Autodesk Fusion 360 part; units mm, degrees
(part 2 of 6)
  spline S17 degree 5 poles (14.0851, -2.1614) (14.0795, -2.1564) (14.0682, -2.1464) (14.0512, -2.1315) (14.0285, -2.1117) (14.0001, -2.0872) (13.9716, -2.0629) (13.9431, -2.0387) (13.9144, -2.0147) (13.8857, -1.9909) (13.8569, -1.9673) (13.828, -1.9439) (13.7991, -1.9206) (13.7701, -1.8976) (13.741, -1.8748) (13.7119, -1.8521) (13.6826, -1.8296) (13.6533, -1.8073) (13.624, -1.7853) (13.5945, -1.7634) (13.565, -1.7417) (13.5354, -1.7202) (13.5058, -1.699) (13.4761, -1.6779) (13.4463, -1.657) (13.4165, -1.6364) (13.3865, -1.6159) (13.3566, -1.5957) (13.3265, -1.5756) (13.2964, -1.5558) (13.2662, -1.5362) (13.236, -1.5168) (13.2057, -1.4977) (13.1753, -1.4788) (13.1449, -1.46) (13.1143, -1.4416) (13.0838, -1.4233) (13.0532, -1.4053) (13.0225, -1.3875) (12.9917, -1.37) (12.9609, -1.3526) (12.93, -1.3356) (12.8991, -1.3188) (12.8681, -1.3022) (12.837, -1.2859) (12.8059, -1.2699) (12.7747, -1.2541) (12.7435, -1.2386) (12.7121, -1.2233) (12.6808, -1.2083) (12.6494, -1.1936) (12.6179, -1.1792) (12.5863, -1.1651) (12.5547, -1.1513) (12.5231, -1.1378) (12.4913, -1.1246) (12.4596, -1.1117) (12.4277, -1.0991) (12.3958, -1.0868) (12.3639, -1.0748) (12.3319, -1.0632) (12.2998, -1.0521) (12.2676, -1.0415) (12.2354, -1.0314) (12.2031, -1.0217) (12.1707, -1.0123) (12.1383, -1.0032) (12.1059, -0.9944) (12.0735, -0.9859) (12.041, -0.978) (12.0083, -0.9712) (11.9821, -0.9669) (11.9622, -0.9645) (11.949, -0.9632) (11.9423, -0.9627) knots -1 -1 -1 -1 -1 -1 -0.98571429 -0.97142857 -0.95714286 -0.94285714 -0.92857143 -0.91428571 -0.9 -0.88571429 -0.87142857 -0.85714286 -0.84285714 -0.82857143 -0.81428571 -0.8 -0.78571429 -0.77142857 -0.75714286 -0.74285714 -0.72857143 -0.71428571 -0.7 -0.68571429 -0.67142857 -0.65714286 -0.64285714 -0.62857143 -0.61428571 -0.6 -0.58571429 -0.57142857 -0.55714286 -0.54285714 -0.52857143 -0.51428571 -0.5 -0.48571429 -0.47142857 -0.45714286 -0.44285714 -0.42857143 -0.41428571 -0.4 -0.38571429 -0.37142857 -0.35714286 -0.34285714 -0.32857143 -0.31428571 -0.3 -0.28571429 -0.27142857 -0.25714286 -0.24285714 -0.22857143 -0.21428571 -0.2 -0.18571429 -0.17142857 -0.15714286 -0.14285714 -0.12857143 -0.11428571 -0.1 -0.08571429 -0.07142857 -0.05714286 -0.04285714 -0.02857143 -0.01428571 0 0 0 0 0 0
  line L17 (11.9423, -0.9627) -> (11.6333, -0.9375)
  arc A35 (10.8984, -0.1305) -> (11.6333, -0.9375) centre (11.6984, -0.1401) ccw
  arc A36 (10.8984, -0.1305) -> (10.8984, 0.1305) centre (0, 0) ccw
  arc A37 (11.6333, 0.9375) -> (10.8984, 0.1305) centre (11.6984, 0.1401) ccw
  line L18 (11.6333, 0.9375) -> (11.9423, 0.9627)
  spline S18 degree 5 poles (11.9423, 0.9627) (11.949, 0.9632) (11.9622, 0.9645) (11.9821, 0.9669) (12.0083, 0.9712) (12.041, 0.978) (12.0735, 0.9859) (12.1059, 0.9944) (12.1383, 1.0032) (12.1707, 1.0123) (12.2031, 1.0217) (12.2354, 1.0314) (12.2676, 1.0415) (12.2998, 1.0521) (12.3319, 1.0632) (12.3639, 1.0748) (12.3958, 1.0868) (12.4277, 1.0991) (12.4596, 1.1117) (12.4913, 1.1246) (12.5231, 1.1378) (12.5547, 1.1513) (12.5863, 1.1651) (12.6179, 1.1792) (12.6494, 1.1936) (12.6808, 1.2083) (12.7121, 1.2233) (12.7435, 1.2386) (12.7747, 1.2541) (12.8059, 1.2699) (12.837, 1.2859) (12.8681, 1.3022) (12.8991, 1.3188) (12.93, 1.3356) (12.9609, 1.3526) (12.9917, 1.37) (13.0225, 1.3875) (13.0532, 1.4053) (13.0838, 1.4233) (13.1143, 1.4416) (13.1449, 1.46) (13.1753, 1.4788) (13.2057, 1.4977) (13.236, 1.5168) (13.2662, 1.5362) (13.2964, 1.5558) (13.3265, 1.5756) (13.3566, 1.5957) (13.3865, 1.6159) (13.4165, 1.6364) (13.4463, 1.657) (13.4761, 1.6779) (13.5058, 1.699) (13.5354, 1.7202) (13.565, 1.7417) (13.5945, 1.7634) (13.624, 1.7853) (13.6533, 1.8073) (13.6826, 1.8296) (13.7119, 1.8521) (13.741, 1.8748) (13.7701, 1.8976) (13.7991, 1.9206) (13.828, 1.9439) (13.8569, 1.9673) (13.8857, 1.9909) (13.9144, 2.0147) (13.9431, 2.0387) (13.9716, 2.0629) (14.0001, 2.0872) (14.0285, 2.1117) (14.0512, 2.1315) (14.0682, 2.1464) (14.0795, 2.1564) (14.0851, 2.1614) knots 0 0 0 0 0 0 0.01428571 0.02857143 0.04285714 0.05714286 0.07142857 0.08571429 0.1 0.11428571 0.12857143 0.14285714 0.15714286 0.17142857 0.18571429 0.2 0.21428571 0.22857143 0.24285714 0.25714286 0.27142857 0.28571429 0.3 0.31428571 0.32857143 0.34285714 0.35714286 0.37142857 0.38571429 0.4 0.41428571 0.42857143 0.44285714 0.45714286 0.47142857 0.48571429 0.5 0.51428571 0.52857143 0.54285714 0.55714286 0.57142857 0.58571429 0.6 0.61428571 0.62857143 0.64285714 0.65714286 0.67142857 0.68571429 0.7 0.71428571 0.72857143 0.74285714 0.75714286 0.77142857 0.78571429 0.8 0.81428571 0.82857143 0.84285714 0.85714286 0.87142857 0.88571429 0.9 0.91428571 0.92857143 0.94285714 0.95714286 0.97142857 0.98571429 1 1 1 1 1 1
  arc A38 (14.0851, 2.1614) -> (13.9148, 3.0727) centre (0, 0) ccw
  spline S19 degree 5 poles (13.9148, 3.0727) (13.9077, 3.0753) (13.8936, 3.0806) (13.8724, 3.0883) (13.8441, 3.0986) (13.8087, 3.1112) (13.7733, 3.1236) (13.738, 3.1358) (13.7026, 3.1478) (13.6672, 3.1596) (13.6319, 3.1712) (13.5965, 3.1826) (13.5611, 3.1939) (13.5257, 3.2049) (13.4903, 3.2157) (13.455, 3.2263) (13.4196, 3.2367) (13.3842, 3.2469) (13.3489, 3.2568) (13.3135, 3.2666) (13.2782, 3.2762) (13.2428, 3.2855) (13.2075, 3.2946) (13.1722, 3.3035) (13.1369, 3.3122) (13.1016, 3.3207) (13.0663, 3.329) (13.031, 3.337) (12.9958, 3.3449) (12.9606, 3.3525) (12.9253, 3.3598) (12.8901, 3.367) (12.8549, 3.3739) (12.8198, 3.3806) (12.7846, 3.387) (12.7495, 3.3932) (12.7144, 3.3992) (12.6794, 3.4049) (12.6443, 3.4104) (12.6093, 3.4157) (12.5743, 3.4207) (12.5393, 3.4255) (12.5044, 3.43) (12.4695, 3.4342) (12.4347, 3.4382) (12.3999, 3.4419) (12.3651, 3.4454) (12.3303, 3.4485) (12.2956, 3.4515) (12.261, 3.4541) (12.2263, 3.4565) (12.1918, 3.4586) (12.1573, 3.4603) (12.1228, 3.4618) (12.0884, 3.4629) (12.0541, 3.4637) (12.0198, 3.4643) (11.9855, 3.4645) (11.9514, 3.4645) (11.9173, 3.4641) (11.8832, 3.4634) (11.8493, 3.4622) (11.8155, 3.4604) (11.7817, 3.4582) (11.7481, 3.4556) (11.7146, 3.4526) (11.6811, 3.4494) (11.6477, 3.4459) (11.6144, 3.4421) (11.5812, 3.4377) (11.5483, 3.4323) (11.5222, 3.4268) (11.5029, 3.4219) (11.4901, 3.4183) (11.4837, 3.4164) knots -1 -1 -1 -1 -1 -1 -0.98571429 -0.97142857 -0.95714286 -0.94285714 -0.92857143 -0.91428571 -0.9 -0.88571429 -0.87142857 -0.85714286 -0.84285714 -0.82857143 -0.81428571 -0.8 -0.78571429 -0.77142857 -0.75714286 -0.74285714 -0.72857143 -0.71428571 -0.7 -0.68571429 -0.67142857 -0.65714286 -0.64285714 -0.62857143 -0.61428571 -0.6 -0.58571429 -0.57142857 -0.55714286 -0.54285714 -0.52857143 -0.51428571 -0.5 -0.48571429 -0.47142857 -0.45714286 -0.44285714 -0.42857143 -0.41428571 -0.4 -0.38571429 -0.37142857 -0.35714286 -0.34285714 -0.32857143 -0.31428571 -0.3 -0.28571429 -0.27142857 -0.25714286 -0.24285714 -0.22857143 -0.21428571 -0.2 -0.18571429 -0.17142857 -0.15714286 -0.14285714 -0.12857143 -0.11428571 -0.1 -0.08571429 -0.07142857 -0.05714286 -0.04285714 -0.02857143 -0.01428571 0 0 0 0 0 0
  line L19 (11.4837, 3.4164) -> (11.1864, 3.3283)
  arc A39 (10.2096, 3.8152) -> (11.1864, 3.3283) centre (10.959, 4.0953) ccw
  arc A40 (10.2096, 3.8152) -> (10.1153, 4.0587) centre (0, 0) ccw
  arc A41 (10.5091, 5.0766) -> (10.1153, 4.0587) centre (10.8578, 4.3566) ccw
  line L20 (10.5091, 5.0766) -> (10.7881, 5.2117)
  spline S20 degree 5 poles (10.7881, 5.2117) (10.7941, 5.2146) (10.806, 5.2206) (10.8236, 5.2301) (10.8466, 5.2436) (10.8746, 5.2617) (10.9021, 5.2808) (10.9292, 5.3004) (10.9563, 5.3204) (10.9832, 5.3406) (11.01, 5.361) (11.0366, 5.3817) (11.063, 5.4027) (11.0892, 5.4242) (11.1151, 5.4462) (11.1407, 5.4686) (11.1662, 5.4913) (11.1915, 5.5143) (11.2166, 5.5376) (11.2416, 5.5611) (11.2664, 5.5848) (11.291, 5.6088) (11.3155, 5.6331) (11.3399, 5.6576) (11.364, 5.6824) (11.388, 5.7075) (11.4118, 5.7328) (11.4355, 5.7584) (11.459, 5.7842) (11.4824, 5.8101) (11.5056, 5.8363) (11.5287, 5.8628) (11.5516, 5.8894) (11.5744, 5.9163) (11.597, 5.9433) (11.6195, 5.9706) (11.6419, 5.9981) (11.6641, 6.0257) (11.6861, 6.0536) (11.708, 6.0817) (11.7298, 6.1099) (11.7514, 6.1384) (11.7729, 6.167) (11.7942, 6.1958) (11.8154, 6.2248) (11.8365, 6.254) (11.8574, 6.2833) (11.8782, 6.3129) (11.8989, 6.3426) (11.9194, 6.3724) (11.9397, 6.4025) (11.96, 6.4327) (11.9801, 6.4631) (12, 6.4936) (12.0198, 6.5243) (12.0395, 6.5552) (12.0591, 6.5863) (12.0785, 6.6175) (12.0977, 6.6488) (12.1169, 6.6803) (12.1359, 6.712) (12.1547, 6.7438) (12.1735, 6.7758) (12.1921, 6.8079) (12.2105, 6.8402) (12.2288, 6.8726) (12.247, 6.9051) (12.2651, 6.9378) (12.283, 6.9707) (12.3007, 7.0037) (12.3184, 7.0368) (12.3324, 7.0634) (12.3428, 7.0835) (12.3498, 7.0969) (12.3532, 7.1036) knots 0 0 0 0 0 0 0.01428571 0.02857143 0.04285714 0.05714286 0.07142857 0.08571429 0.1 0.11428571 0.12857143 0.14285714 0.15714286 0.17142857 0.18571429 0.2 0.21428571 0.22857143 0.24285714 0.25714286 0.27142857 0.28571429 0.3 0.31428571 0.32857143 0.34285714 0.35714286 0.37142857 0.38571429 0.4 0.41428571 0.42857143 0.44285714 0.45714286 0.47142857 0.48571429 0.5 0.51428571 0.52857143 0.54285714 0.55714286 0.57142857 0.58571429 0.6 0.61428571 0.62857143 0.64285714 0.65714286 0.67142857 0.68571429 0.7 0.71428571 0.72857143 0.74285714 0.75714286 0.77142857 0.78571429 0.8 0.81428571 0.82857143 0.84285714 0.85714286 0.87142857 0.88571429 0.9 0.91428571 0.92857143 0.94285714 0.95714286 0.97142857 0.98571429 1 1 1 1 1 1
  arc A42 (12.3532, 7.1036) -> (11.8651, 7.8918) centre (0, 0) ccw
  spline S21 degree 5 poles (11.8651, 7.8918) (11.8576, 7.8917) (11.8425, 7.8915) (11.82, 7.891) (11.7899, 7.8904) (11.7524, 7.8894) (11.7149, 7.8882) (11.6775, 7.8868) (11.6402, 7.8852) (11.6029, 7.8834) (11.5657, 7.8815) (11.5286, 7.8793) (11.4916, 7.877) (11.4546, 7.8745) (11.4177, 7.8718) (11.3809, 7.8689) (11.3442, 7.8658) (11.3075, 7.8625) (11.271, 7.8591) (11.2345, 7.8554) (11.1981, 7.8516) (11.1617, 7.8475) (11.1255, 7.8433) (11.0893, 7.8388) (11.0533, 7.8342) (11.0173, 7.8293) (10.9814, 7.8243) (10.9456, 7.8191) (10.9099, 7.8136) (10.8743, 7.808) (10.8388, 7.8021) (10.8034, 7.7961) (10.7681, 7.7898) (10.7329, 7.7833) (10.6978, 7.7766) (10.6628, 7.7697) (10.6279, 7.7626) (10.5931, 7.7553) (10.5585, 7.7478) (10.5239, 7.74) (10.4895, 7.7321) (10.4552, 7.7239) (10.421, 7.7155) (10.3869, 7.7068) (10.353, 7.6979) (10.3192, 7.6888) (10.2855, 7.6795) (10.2519, 7.6699) (10.2185, 7.6601) (10.1852, 7.6501) (10.1521, 7.6398) (10.1191, 7.6292) (10.0863, 7.6184) (10.0537, 7.6073) (10.0212, 7.5959) (9.9889, 7.5842) (9.9567, 7.5724) (9.9247, 7.5603) (9.8928, 7.5479) (9.8611, 7.5352) (9.8297, 7.5222) (9.7985, 7.5088) (9.7675, 7.495) (9.7369, 7.4807) (9.7065, 7.4661) (9.6763, 7.4512) (9.6462, 7.4362) (9.6163, 7.4209) (9.5866, 7.4053) (9.5573, 7.3892) (9.5286, 7.3722) (9.5063, 7.3577) (9.49, 7.3461) (9.4793, 7.3382) (9.474, 7.3341) knots -1 -1 -1 -1 -1 -1 -0.98571429 -0.97142857 -0.95714286 -0.94285714 -0.92857143 -0.91428571 -0.9 -0.88571429 -0.87142857 -0.85714286 -0.84285714 -0.82857143 -0.81428571 -0.8 -0.78571429 -0.77142857 -0.75714286 -0.74285714 -0.72857143 -0.71428571 -0.7 -0.68571429 -0.67142857 -0.65714286 -0.64285714 -0.62857143 -0.61428571 -0.6 -0.58571429 -0.57142857 -0.55714286 -0.54285714 -0.52857143 -0.51428571 -0.5 -0.48571429 -0.47142857 -0.45714286 -0.44285714 -0.42857143 -0.41428571 -0.4 -0.38571429 -0.37142857 -0.35714286 -0.34285714 -0.32857143 -0.31428571 -0.3 -0.28571429 -0.27142857 -0.25714286 -0.24285714 -0.22857143 -0.21428571 -0.2 -0.18571429 -0.17142857 -0.15714286 -0.14285714 -0.12857143 -0.11428571 -0.1 -0.08571429 -0.07142857 -0.05714286 -0.04285714 -0.02857143 -0.01428571 0 0 0 0 0 0
  line L21 (9.474, 7.3341) -> (9.2287, 7.1445)
  arc A43 (8.142, 7.2457) -> (9.2287, 7.1445) centre (8.7396, 7.7776) ccw
  arc A44 (8.142, 7.2457) -> (7.9661, 7.4387) centre (0, 0) ccw
  arc A45 (7.9656, 8.5301) -> (7.9661, 7.4387) centre (8.5508, 7.9847) ccw
  line L22 (7.9656, 8.5301) -> (8.1769, 8.7569)
  spline S22 degree 5 poles (8.1769, 8.7569) (8.1815, 8.7618) (8.1904, 8.7717) (8.2034, 8.7868) (8.2199, 8.8077) (8.2395, 8.8347) (8.2582, 8.8624) (8.2765, 8.8906) (8.2945, 8.919) (8.3123, 8.9475) (8.3299, 8.9762) (8.3472, 9.0051) (8.3643, 9.0343) (8.3809, 9.0638) (8.3971, 9.0937) (8.413, 9.1238) (8.4285, 9.1542) (8.4437, 9.1848) (8.4588, 9.2155) (8.4735, 9.2465) (8.4881, 9.2776) (8.5024, 9.3089) (8.5165, 9.3404) (8.5303, 9.372) (8.5439, 9.4039) (8.5572, 9.4359) (8.5703, 9.4681) (8.5831, 9.5005) (8.5957, 9.533) (8.6081, 9.5657) (8.6203, 9.5985) (8.6323, 9.6315) (8.6441, 9.6646) (8.6556, 9.6979) (8.6669, 9.7313) (8.6781, 9.7649) (8.689, 9.7986) (8.6997, 9.8324) (8.7102, 9.8663) (8.7204, 9.9004) (8.7305, 9.9346) (8.7404, 9.9689) (8.7501, 10.0034) (8.7596, 10.038) (8.7689, 10.0727) (8.778, 10.1075) (8.7869, 10.1424) (8.7956, 10.1775) (8.8042, 10.2126) (8.8125, 10.2479) (8.8206, 10.2833) (8.8286, 10.3188) (8.8363, 10.3543) (8.8439, 10.39) (8.8513, 10.4258) (8.8585, 10.4617) (8.8655, 10.4977) (8.8723, 10.5338) (8.879, 10.57) (8.8854, 10.6063) (8.8917, 10.6427) (8.8978, 10.6792) (8.9037, 10.7158) (8.9095, 10.7524) (8.915, 10.7892) (8.9204, 10.826) (8.9256, 10.863) (8.9306, 10.9) (8.9354, 10.9371) (8.9401, 10.9743) (8.9446, 11.0116) (8.948, 11.0414) (8.9505, 11.0639) (8.9521, 11.0789) (8.9529, 11.0864) knots 0 0 0 0 0 0 0.01428571 0.02857143 0.04285714 0.05714286 0.07142857 0.08571429 0.1 0.11428571 0.12857143 0.14285714 0.15714286 0.17142857 0.18571429 0.2 0.21428571 0.22857143 0.24285714 0.25714286 0.27142857 0.28571429 0.3 0.31428571 0.32857143 0.34285714 0.35714286 0.37142857 0.38571429 0.4 0.41428571 0.42857143 0.44285714 0.45714286 0.47142857 0.48571429 0.5 0.51428571 0.52857143 0.54285714 0.55714286 0.57142857 0.58571429 0.6 0.61428571 0.62857143 0.64285714 0.65714286 0.67142857 0.68571429 0.7 0.71428571 0.72857143 0.74285714 0.75714286 0.77142857 0.78571429 0.8 0.81428571 0.82857143 0.84285714 0.85714286 0.87142857 0.88571429 0.9 0.91428571 0.92857143 0.94285714 0.95714286 0.97142857 0.98571429 1 1 1 1 1 1
  arc A46 (8.9529, 11.0864) -> (8.2131, 11.6451) centre (0, 0) ccw
  spline S23 degree 5 poles (8.2131, 11.6451) (8.2061, 11.6423) (8.1921, 11.6366) (8.1712, 11.628) (8.1434, 11.6166) (8.1088, 11.602) (8.0743, 11.5874) (8.0399, 11.5726) (8.0057, 11.5576) (7.9716, 11.5425) (7.9376, 11.5273) (7.9038, 11.5119) (7.8701, 11.4963) (7.8365, 11.4806) (7.8031, 11.4648) (7.7698, 11.4488) (7.7367, 11.4327) (7.7037, 11.4164) (7.6708, 11.3999) (7.6381, 11.3833) (7.6056, 11.3666) (7.5732, 11.3497) (7.5409, 11.3326) (7.5088, 11.3154) (7.4768, 11.298) (7.445, 11.2805) (7.4134, 11.2629) (7.3819, 11.2451) (7.3506, 11.2271) (7.3194, 11.209) (7.2884, 11.1907) (7.2576, 11.1722) (7.2269, 11.1537) (7.1965, 11.1349) (7.1661, 11.116) (7.136, 11.0969) (7.106, 11.0777) (7.0763, 11.0583) (7.0467, 11.0388) (7.0172, 11.0191) (6.988, 10.9992) (6.959, 10.9791) (6.9301, 10.9589) (6.9015, 10.9386) (6.8731, 10.918) (6.8448, 10.8973) (6.8168, 10.8764) (6.789, 10.8554) (6.7613, 10.8342) (6.7339, 10.8128) (6.7067, 10.7912) (6.6798, 10.7695) (6.6531, 10.7475) (6.6267, 10.7254) (6.6005, 10.703) (6.5746, 10.6805) (6.5489, 10.6578) (6.5234, 10.6349) (6.4981, 10.6119) (6.4732, 10.5886) (6.4485, 10.5651) (6.4243, 10.5414) (6.4005, 10.5173) (6.377, 10.493) (6.354, 10.4683) (6.3312, 10.4436) (6.3086, 10.4186) (6.2862, 10.3936) (6.2642, 10.3683) (6.2426, 10.3427) (6.222, 10.3165) (6.2064, 10.2949) (6.1954, 10.2783) (6.1884, 10.2669) (6.1849, 10.2612) knots -1 -1 -1 -1 -1 -1 -0.98571429 -0.97142857 -0.95714286 -0.94285714 -0.92857143 -0.91428571 -0.9 -0.88571429 -0.87142857 -0.85714286 -0.84285714 -0.82857143 -0.81428571 -0.8 -0.78571429 -0.77142857 -0.75714286 -0.74285714 -0.72857143 -0.71428571 -0.7 -0.68571429 -0.67142857 -0.65714286 -0.64285714 -0.62857143 -0.61428571 -0.6 -0.58571429 -0.57142857 -0.55714286 -0.54285714 -0.52857143 -0.51428571 -0.5 -0.48571429 -0.47142857 -0.45714286 -0.44285714 -0.42857143 -0.41428571 -0.4 -0.38571429 -0.37142857 -0.35714286 -0.34285714 -0.32857143 -0.31428571 -0.3 -0.28571429 -0.27142857 -0.25714286 -0.24285714 -0.22857143 -0.21428571 -0.2 -0.18571429 -0.17142857 -0.15714286 -0.14285714 -0.12857143 -0.11428571 -0.1 -0.08571429 -0.07142857 -0.05714286 -0.04285714 -0.02857143 -0.01428571 0 0 0 0 0 0
  line L23 (6.1849, 10.2612) -> (6.0246, 9.9959)
  arc A47 (4.9747, 9.6977) -> (6.0246, 9.9959) centre (5.3398, 10.4095) ccw
  arc A48 (4.9747, 9.6977) -> (4.741, 9.8141) centre (0, 0) ccw
  arc A49 (4.3462, 10.8316) -> (4.741, 9.8141) centre (5.089, 10.5344) ccw
  line L24 (4.3462, 10.8316) -> (4.4614, 11.1194)
  spline S24 degree 5 poles (4.4614, 11.1194) (4.4639, 11.1256) (4.4687, 11.1381) (4.4753, 11.1569) (4.4832, 11.1823) (4.4916, 11.2146) (4.4991, 11.2472) (4.5059, 11.28) (4.5125, 11.313) (4.5188, 11.346) (4.5248, 11.3792) (4.5305, 11.4124) (4.5359, 11.4458) (4.5407, 11.4793) (4.5451, 11.513) (4.549, 11.5468) (4.5525, 11.5807) (4.5556, 11.6148) (4.5585, 11.6489) (4.5611, 11.6831) (4.5635, 11.7173) (4.5655, 11.7517) (4.5673, 11.7861) (4.5687, 11.8207) (4.5699, 11.8553) (4.5707, 11.89) (4.5713, 11.9247) (4.5715, 11.9595) (4.5716, 11.9944) (4.5713, 12.0294) (4.5708, 12.0644) (4.5701, 12.0995) (4.5691, 12.1346) (4.5678, 12.1698) (4.5663, 12.205) (4.5646, 12.2403) (4.5626, 12.2757) (4.5603, 12.3111) (4.5578, 12.3465) (4.5551, 12.382) (4.5522, 12.4176) (4.549, 12.4532) (4.5456, 12.4888) (4.542, 12.5245) (4.5381, 12.5602) (4.534, 12.5959) (4.5297, 12.6317) (4.5252, 12.6676) (4.5204, 12.7034) (4.5154, 12.7393) (4.5102, 12.7752) (4.5048, 12.8112) (4.4992, 12.8472) (4.4934, 12.8832) (4.4873, 12.9193) (4.4811, 12.9553) (4.4746, 12.9914) (4.4679, 13.0276) (4.4611, 13.0637) (4.454, 13.0999) (4.4467, 13.1361) (4.4392, 13.1723) (4.4315, 13.2086) (4.4236, 13.2448) (4.4155, 13.2811) (4.4072, 13.3174) (4.3987, 13.3537) (4.39, 13.39) (4.3811, 13.4264) (4.372, 13.4627) (4.3627, 13.4991) (4.3551, 13.5282) (4.3493, 13.5501) (4.3455, 13.5646) (4.3435, 13.5719) knots 0 0 0 0 0 0 0.01428571 0.02857143 0.04285714 0.05714286 0.07142857 0.08571429 0.1 0.11428571 0.12857143 0.14285714 0.15714286 0.17142857 0.18571429 0.2 0.21428571 0.22857143 0.24285714 0.25714286 0.27142857 0.28571429 0.3 0.31428571 0.32857143 0.34285714 0.35714286 0.37142857 0.38571429 0.4 0.41428571 0.42857143 0.44285714 0.45714286 0.47142857 0.48571429 0.5 0.51428571 0.52857143 0.54285714 0.55714286 0.57142857 0.58571429 0.6 0.61428571 0.62857143 0.64285714 0.65714286 0.67142857 0.68571429 0.7 0.71428571 0.72857143 0.74285714 0.75714286 0.77142857 0.78571429 0.8 0.81428571 0.82857143 0.84285714 0.85714286 0.87142857 0.88571429 0.9 0.91428571 0.92857143 0.94285714 0.95714286 0.97142857 0.98571429 1 1 1 1 1 1
  arc A50 (4.3435, 13.5719) -> (3.4518, 13.8256) centre (0, 0) ccw
  spline S25 degree 5 poles (3.4518, 13.8256) (3.4463, 13.8205) (3.4353, 13.8101) (3.4189, 13.7946) (3.3971, 13.7738) (3.3701, 13.7478) (3.3432, 13.7217) (3.3165, 13.6955) (3.29, 13.6692) (3.2636, 13.6428) (3.2375, 13.6163) (3.2115, 13.5897) (3.1857, 13.563) (3.1601, 13.5363) (3.1346, 13.5094) (3.1094, 13.4825) (3.0843, 13.4554) (3.0594, 13.4283) (3.0347, 13.4011) (3.0102, 13.3738) (2.9859, 13.3465) (2.9618, 13.319) (2.9379, 13.2914) (2.9141, 13.2638) (2.8906, 13.2361) (2.8673, 13.2082) (2.8442, 13.1803) (2.8212, 13.1524) (2.7985, 13.1243) (2.776, 13.0961) (2.7537, 13.0679) (2.7316, 13.0396) (2.7098, 13.0111) (2.6881, 12.9826) (2.6667, 12.9541) (2.6455, 12.9254) (2.6245, 12.8966) (2.6037, 12.8678) (2.5831, 12.8389) (2.5628, 12.8099) (2.5428, 12.7808) (2.5229, 12.7516) (2.5033, 12.7224) (2.484, 12.693) (2.4649, 12.6636) (2.446, 12.6341) (2.4274, 12.6045) (2.4091, 12.5748) (2.391, 12.5451) (2.3732, 12.5152) (2.3556, 12.4853) (2.3384, 12.4553) (2.3214, 12.4251) (2.3048, 12.3949) (2.2884, 12.3647) (2.2724, 12.3343) (2.2566, 12.3038) (2.2411, 12.2733) (2.2259, 12.2427) (2.211, 12.212) (2.1965, 12.1812) (2.1825, 12.1503) (2.169, 12.1192) (2.1559, 12.088) (2.1433, 12.0568) (2.131, 12.0254) (2.1189, 11.994) (2.1071, 11.9626) (2.0957, 11.931) (2.0849, 11.8994) (2.0751, 11.8675) (2.0684, 11.8417) (2.0641, 11.8222) (2.0616, 11.8091) (2.0605, 11.8026) knots -1 -1 -1 -1 -1 -1 -0.98571429 -0.97142857 -0.95714286 -0.94285714 -0.92857143 -0.91428571 -0.9 -0.88571429 -0.87142857 -0.85714286 -0.84285714 -0.82857143 -0.81428571 -0.8 -0.78571429 -0.77142857 -0.75714286 -0.74285714 -0.72857143 -0.71428571 -0.7 -0.68571429 -0.67142857 -0.65714286 -0.64285714 -0.62857143 -0.61428571 -0.6 -0.58571429 -0.57142857 -0.55714286 -0.54285714 -0.52857143 -0.51428571 -0.5 -0.48571429 -0.47142857 -0.45714286 -0.44285714 -0.42857143 -0.41428571 -0.4 -0.38571429 -0.37142857 -0.35714286 -0.34285714 -0.32857143 -0.31428571 -0.3 -0.28571429 -0.27142857 -0.25714286 -0.24285714 -0.22857143 -0.21428571 -0.2 -0.18571429 -0.17142857 -0.15714286 -0.14285714 -0.12857143 -0.11428571 -0.1 -0.08571429 -0.07142857 -0.05714286 -0.04285714 -0.02857143 -0.01428571 0 0 0 0 0 0
  line L25 (2.0605, 11.8026) -> (2.0069, 11.4972)
  arc A51 (1.1356, 10.8399) -> (2.0069, 11.4972) centre (1.2189, 11.6355) ccw
  arc A52 (1.1356, 10.8399) -> (0.8756, 10.864) centre (0, 0) ccw
  arc A53 (0.1399, 11.6702) -> (0.8756, 10.864) centre (0.9399, 11.6614) ccw
  line L26 (0.1399, 11.6702) -> (0.1433, 11.9802)
  spline S26 degree 5 poles (0.1433, 11.9802) (0.1434, 11.9869) (0.1434, 12.0002) (0.1428, 12.0202) (0.1409, 12.0467) (0.1371, 12.0799) (0.1323, 12.113) (0.1269, 12.1461) (0.121, 12.1791) (0.115, 12.2122) (0.1086, 12.2453) (0.102, 12.2784) (0.0949, 12.3114) (0.0873, 12.3444) (0.0792, 12.3774) (0.0706, 12.4103) (0.0616, 12.4432) (0.0523, 12.4761) (0.0426, 12.509) (0.0327, 12.5418) (0.0225, 12.5746) (0.012, 12.6074) (0.0012, 12.6401) (-0.0099, 12.6729) (-0.0213, 12.7055) (-0.0331, 12.7382) (-0.0451, 12.7708) (-0.0575, 12.8034) (-0.07, 12.8359) (-0.0829, 12.8684) (-0.096, 12.9009) (-0.1094, 12.9333) (-0.123, 12.9657) (-0.1369, 12.9981) (-0.151, 13.0304) (-0.1654, 13.0627) (-0.18, 13.0949) (-0.1949, 13.1271) (-0.21, 13.1593) (-0.2254, 13.1914) (-0.241, 13.2235) (-0.2568, 13.2555) (-0.2728, 13.2875) (-0.2891, 13.3195) (-0.3056, 13.3514) (-0.3223, 13.3832) (-0.3393, 13.415) (-0.3565, 13.4468) (-0.3739, 13.4785) (-0.3915, 13.5102) (-0.4093, 13.5418) (-0.4273, 13.5734) (-0.4455, 13.605) (-0.464, 13.6364) (-0.4827, 13.6679) (-0.5015, 13.6992) (-0.5206, 13.7306) (-0.5399, 13.7619) (-0.5593, 13.7931) (-0.579, 13.8242) (-0.5989, 13.8554) (-0.619, 13.8864) (-0.6392, 13.9175) (-0.6597, 13.9484) (-0.6804, 13.9793) (-0.7012, 14.0102) (-0.7223, 14.041) (-0.7435, 14.0717) (-0.7649, 14.1024) (-0.7865, 14.133) (-0.8083, 14.1635) (-0.8259, 14.1879) (-0.8392, 14.2062) (-0.8481, 14.2184) (-0.8525, 14.2245) knots 0 0 0 0 0 0 0.01428571 0.02857143 0.04285714 0.05714286 0.07142857 0.08571429 0.1 0.11428571 0.12857143 0.14285714 0.15714286 0.17142857 0.18571429 0.2 0.21428571 0.22857143 0.24285714 0.25714286 0.27142857 0.28571429 0.3 0.31428571 0.32857143 0.34285714 0.35714286 0.37142857 0.38571429 0.4 0.41428571 0.42857143 0.44285714 0.45714286 0.47142857 0.48571429 0.5 0.51428571 0.52857143 0.54285714 0.55714286 0.57142857 0.58571429 0.6 0.61428571 0.62857143 0.64285714 0.65714286 0.67142857 0.68571429 0.7 0.71428571 0.72857143 0.74285714 0.75714286 0.77142857 0.78571429 0.8 0.81428571 0.82857143 0.84285714 0.85714286 0.87142857 0.88571429 0.9 0.91428571 0.92857143 0.94285714 0.95714286 0.97142857 0.98571429 1 1 1 1 1 1
  arc A54 (-0.8525, 14.2245) -> (-1.7757, 14.1389) centre (0, 0) ccw
  spline S27 degree 5 poles (-1.7757, 14.1389) (-1.779, 14.1321) (-1.7855, 14.1185) (-1.7952, 14.0981) (-1.808, 14.0709) (-1.8238, 14.0369) (-1.8394, 14.0028) (-1.8548, 13.9687) (-1.8701, 13.9346) (-1.8851, 13.9005) (-1.8999, 13.8663) (-1.9145, 13.8321) (-1.929, 13.7979) (-1.9432, 13.7637) (-1.9572, 13.7295) (-1.971, 13.6953) (-1.9847, 13.661) (-1.9981, 13.6267) (-2.0113, 13.5924) (-2.0242, 13.5581) (-2.037, 13.5238) (-2.0496, 13.4895) (-2.0619, 13.4552) (-2.0741, 13.4208) (-2.086, 13.3865) (-2.0977, 13.3521) (-2.1092, 13.3177) (-2.1204, 13.2834) (-2.1315, 13.249) (-2.1423, 13.2146) (-2.1529, 13.1802) (-2.1633, 13.1458) (-2.1734, 13.1114) (-2.1833, 13.077) (-2.1929, 13.0426) (-2.2024, 13.0082) (-2.2116, 12.9738) (-2.2205, 12.9394) (-2.2292, 12.905) (-2.2377, 12.8707) (-2.2459, 12.8363) (-2.2539, 12.8019) (-2.2616, 12.7676) (-2.269, 12.7332) (-2.2762, 12.6989) (-2.2831, 12.6645) (-2.2897, 12.6302) (-2.2961, 12.5959) (-2.3023, 12.5616) (-2.3081, 12.5274) (-2.3137, 12.4931) (-2.3189, 12.4589) (-2.3238, 12.4247) (-2.3284, 12.3905) (-2.3327, 12.3564) (-2.3367, 12.3223) (-2.3404, 12.2882) (-2.3439, 12.2541) (-2.347, 12.22) (-2.3498, 12.186) (-2.3522, 12.1521) (-2.3541, 12.1182) (-2.3555, 12.0843) (-2.3564, 12.0506) (-2.3568, 12.0168) (-2.357, 11.9832) (-2.3569, 11.9495) (-2.3565, 11.9159) (-2.3558, 11.8824) (-2.3545, 11.849) (-2.3521, 11.8157) (-2.349, 11.7893) (-2.346, 11.7695) (-2.3435, 11.7564) (-2.3422, 11.7499) knots -1 -1 -1 -1 -1 -1 -0.98571429 -0.97142857 -0.95714286 -0.94285714 -0.92857143 -0.91428571 -0.9 -0.88571429 -0.87142857 -0.85714286 -0.84285714 -0.82857143 -0.81428571 -0.8 -0.78571429 -0.77142857 -0.75714286 -0.74285714 -0.72857143 -0.71428571 -0.7 -0.68571429 -0.67142857 -0.65714286 -0.64285714 -0.62857143 -0.61428571 -0.6 -0.58571429 -0.57142857 -0.55714286 -0.54285714 -0.52857143 -0.51428571 -0.5 -0.48571429 -0.47142857 -0.45714286 -0.44285714 -0.42857143 -0.41428571 -0.4 -0.38571429 -0.37142857 -0.35714286 -0.34285714 -0.32857143 -0.31428571 -0.3 -0.28571429 -0.27142857 -0.25714286 -0.24285714 -0.22857143 -0.21428571 -0.2 -0.18571429 -0.17142857 -0.15714286 -0.14285714 -0.12857143 -0.11428571 -0.1 -0.08571429 -0.07142857 -0.05714286 -0.04285714 -0.02857143 -0.01428571 0 0 0 0 0 0
  line L27 (-2.3422, 11.7499) -> (-2.2819, 11.4458)
  arc A55 (-2.8569, 10.5181) -> (-2.2819, 11.4458) centre (-3.0666, 11.2901) ccw
  arc A56 (-2.8569, 10.5181) -> (-3.108, 10.4467) centre (0, 0) ccw
  arc A57 (-4.0853, 10.9327) -> (-3.108, 10.4467) centre (-3.3362, 11.2134) ccw
  line L28 (-4.0853, 10.9327) -> (-4.1941, 11.223)
  spline S28 degree 5 poles (-4.1941, 11.223) (-4.1964, 11.2292) (-4.2013, 11.2416) (-4.2091, 11.26) (-4.2204, 11.2841) (-4.2359, 11.3137) (-4.2523, 11.3428) (-4.2694, 11.3717) (-4.2868, 11.4004) (-4.3044, 11.4291) (-4.3222, 11.4576) (-4.3404, 11.4861) (-4.3589, 11.5143) (-4.3779, 11.5424) (-4.3974, 11.5702) (-4.4173, 11.5978) (-4.4376, 11.6252) (-4.4582, 11.6525) (-4.479, 11.6797) (-4.5001, 11.7067) (-4.5215, 11.7336) (-4.5431, 11.7604) (-4.565, 11.787) (-4.5872, 11.8135) (-4.6097, 11.8398) (-4.6324, 11.866) (-4.6554, 11.8921) (-4.6787, 11.918) (-4.7022, 11.9438) (-4.7259, 11.9695) (-4.7498, 11.995) (-4.774, 12.0205) (-4.7984, 12.0458) (-4.8231, 12.0709) (-4.8479, 12.0959) (-4.873, 12.1208) (-4.8983, 12.1456) (-4.9238, 12.1703) (-4.9495, 12.1948) (-4.9754, 12.2192) (-5.0016, 12.2435) (-5.0279, 12.2677) (-5.0544, 12.2917) (-5.0811, 12.3156) (-5.1081, 12.3394) (-5.1352, 12.3631) (-5.1625, 12.3866) (-5.1899, 12.41) (-5.2176, 12.4333) (-5.2455, 12.4565) (-5.2735, 12.4795) (-5.3017, 12.5025) (-5.3301, 12.5253) (-5.3587, 12.548) (-5.3875, 12.5705) (-5.4164, 12.593) (-5.4455, 12.6153) (-5.4748, 12.6375) (-5.5042, 12.6596) (-5.5338, 12.6816) (-5.5636, 12.7034) (-5.5935, 12.7251) (-5.6236, 12.7467) (-5.6539, 12.7682) (-5.6843, 12.7895) (-5.7149, 12.8108) (-5.7457, 12.8319) (-5.7766, 12.8529) (-5.8076, 12.8737) (-5.8388, 12.8945) (-5.8702, 12.9151) (-5.8954, 12.9315) (-5.9144, 12.9438) (-5.9271, 12.9519) (-5.9334, 12.956) knots 0 0 0 0 0 0 0.01428571 0.02857143 0.04285714 0.05714286 0.07142857 0.08571429 0.1 0.11428571 0.12857143 0.14285714 0.15714286 0.17142857 0.18571429 0.2 0.21428571 0.22857143 0.24285714 0.25714286 0.27142857 0.28571429 0.3 0.31428571 0.32857143 0.34285714 0.35714286 0.37142857 0.38571429 0.4 0.41428571 0.42857143 0.44285714 0.45714286 0.47142857 0.48571429 0.5 0.51428571 0.52857143 0.54285714 0.55714286 0.57142857 0.58571429 0.6 0.61428571 0.62857143 0.64285714 0.65714286 0.67142857 0.68571429 0.7 0.71428571 0.72857143 0.74285714 0.75714286 0.77142857 0.78571429 0.8 0.81428571 0.82857143 0.84285714 0.85714286 0.87142857 0.88571429 0.9 0.91428571 0.92857143 0.94285714 0.95714286 0.97142857 0.98571429 1 1 1 1 1 1
  arc A58 (-5.9334, 12.956) -> (-6.7634, 12.5427) centre (0, 0) ccw
  spline S29 degree 5 poles (-6.7634, 12.5427) (-6.764, 12.5352) (-6.7651, 12.5202) (-6.7668, 12.4976) (-6.7689, 12.4676) (-6.7713, 12.4302) (-6.7736, 12.3927) (-6.7757, 12.3554) (-6.7775, 12.3181) (-6.7792, 12.2808) (-6.7807, 12.2436) (-6.782, 12.2065) (-6.7831, 12.1694) (-6.784, 12.1323) (-6.7847, 12.0953) (-6.7852, 12.0584) (-6.7856, 12.0216) (-6.7857, 11.9848) (-6.7856, 11.948) (-6.7853, 11.9113) (-6.7848, 11.8747) (-6.7842, 11.8382) (-6.7833, 11.8017) (-6.7822, 11.7653) (-6.7809, 11.729) (-6.7794, 11.6927) (-6.7777, 11.6565) (-6.7758, 11.6204) (-6.7736, 11.5843) (-6.7713, 11.5483) (-6.7688, 11.5125) (-6.766, 11.4766) (-6.763, 11.4409) (-6.7598, 11.4053) (-6.7564, 11.3697) (-6.7528, 11.3342) (-6.7489, 11.2988) (-6.7448, 11.2635) (-6.7405, 11.2283) (-6.736, 11.1932) (-6.7312, 11.1582) (-6.7262, 11.1232) (-6.721, 11.0884) (-6.7155, 11.0537) (-6.7098, 11.0191) (-6.7039, 10.9846) (-6.6977, 10.9502) (-6.6913, 10.9159) (-6.6846, 10.8817) (-6.6777, 10.8476) (-6.6705, 10.8137) (-6.663, 10.7799) (-6.6552, 10.7462) (-6.6472, 10.7127) (-6.6388, 10.6793) (-6.6302, 10.646) (-6.6214, 10.6129) (-6.6123, 10.5799) (-6.6029, 10.547) (-6.5932, 10.5143) (-6.5832, 10.4818) (-6.5727, 10.4495) (-6.5618, 10.4174) (-6.5504, 10.3856) (-6.5387, 10.354) (-6.5266, 10.3225) (-6.5144, 10.2912) (-6.5019, 10.26) (-6.4892, 10.229) (-6.4758, 10.1983) (-6.4616, 10.1682) (-6.4492, 10.1446) (-6.4392, 10.1273) (-6.4322, 10.116) (-6.4286, 10.1103) knots -1 -1 -1 -1 -1 -1 -0.98571429 -0.97142857 -0.95714286 -0.94285714 -0.92857143 -0.91428571 -0.9 -0.88571429 -0.87142857 -0.85714286 -0.84285714 -0.82857143 -0.81428571 -0.8 -0.78571429 -0.77142857 -0.75714286 -0.74285714 -0.72857143 -0.71428571 -0.7 -0.68571429 -0.67142857 -0.65714286 -0.64285714 -0.62857143 -0.61428571 -0.6 -0.58571429 -0.57142857 -0.55714286 -0.54285714 -0.52857143 -0.51428571 -0.5 -0.48571429 -0.47142857 -0.45714286 -0.44285714 -0.42857143 -0.41428571 -0.4 -0.38571429 -0.37142857 -0.35714286 -0.34285714 -0.32857143 -0.31428571 -0.3 -0.28571429 -0.27142857 -0.25714286 -0.24285714 -0.22857143 -0.21428571 -0.2 -0.18571429 -0.17142857 -0.15714286 -0.14285714 -0.12857143 -0.11428571 -0.1 -0.08571429 -0.07142857 -0.05714286 -0.04285714 -0.02857143 -0.01428571 0 0 0 0 0 0
  line L29 (-6.4286, 10.1103) -> (-6.2625, 9.8485)
  arc A59 (-6.4636, 8.7758) -> (-6.2625, 9.8485) centre (-6.938, 9.4199) ccw
  arc A60 (-6.4636, 8.7758) -> (-6.6719, 8.6185) centre (0, 0) ccw
  arc A61 (-7.7588, 8.7186) -> (-6.6719, 8.6185) centre (-7.1617, 9.2511) ccw
  line L30 (-7.7588, 8.7186) -> (-7.9651, 8.9501)
  spline S30 degree 5 poles (-7.9651, 8.9501) (-7.9695, 8.955) (-7.9785, 8.9648) (-7.9924, 8.9792) (-8.0117, 8.9976) (-8.0368, 9.0195) (-8.0627, 9.0407) (-8.089, 9.0615) (-8.1156, 9.082) (-8.1424, 9.1024) (-8.1693, 9.1226) (-8.1965, 9.1425) (-8.224, 9.1622) (-8.2519, 9.1814) (-8.2801, 9.2003) (-8.3086, 9.2189) (-8.3374, 9.2372) (-8.3665, 9.2552) (-8.3957, 9.273) (-8.4252, 9.2906) (-8.4548, 9.3079) (-8.4847, 9.3251) (-8.5147, 9.342) (-8.545, 9.3587) (-8.5754, 9.3751) (-8.6061, 9.3913) (-8.637, 9.4073) (-8.668, 9.4231) (-8.6993, 9.4387) (-8.7306, 9.454) (-8.7622, 9.4692) (-8.7939, 9.4842) (-8.8258, 9.4989) (-8.8579, 9.5135) (-8.8901, 9.5279) (-8.9225, 9.542) (-8.955, 9.556) (-8.9877, 9.5698) (-9.0206, 9.5833) (-9.0536, 9.5967) (-9.0867, 9.6099) (-9.12, 9.623) (-9.1534, 9.6358) (-9.1869, 9.6484) (-9.2206, 9.6609) (-9.2544, 9.6732) (-9.2884, 9.6853) (-9.3225, 9.6972) (-9.3567, 9.7089) (-9.3911, 9.7204) (-9.4255, 9.7318) (-9.4601, 9.743) (-9.4949, 9.754) (-9.5297, 9.7648) (-9.5647, 9.7755) (-9.5998, 9.786) (-9.635, 9.7963) (-9.6703, 9.8064) (-9.7057, 9.8164) (-9.7412, 9.8262) (-9.7769, 9.8358) (-9.8127, 9.8452) (-9.8485, 9.8545) (-9.8845, 9.8636) (-9.9206, 9.8725) (-9.9568, 9.8812) (-9.9931, 9.8898) (-10.0295, 9.8982) (-10.066, 9.9064) (-10.1026, 9.9145) (-10.1393, 9.9224) (-10.1687, 9.9286) (-10.1908, 9.9332) (-10.2056, 9.9362) (-10.213, 9.9377) knots 0 0 0 0 0 0 0.01428571 0.02857143 0.04285714 0.05714286 0.07142857 0.08571429 0.1 0.11428571 0.12857143 0.14285714 0.15714286 0.17142857 0.18571429 0.2 0.21428571 0.22857143 0.24285714 0.25714286 0.27142857 0.28571429 0.3 0.31428571 0.32857143 0.34285714 0.35714286 0.37142857 0.38571429 0.4 0.41428571 0.42857143 0.44285714 0.45714286 0.47142857 0.48571429 0.5 0.51428571 0.52857143 0.54285714 0.55714286 0.57142857 0.58571429 0.6 0.61428571 0.62857143 0.64285714 0.65714286 0.67142857 0.68571429 0.7 0.71428571 0.72857143 0.74285714 0.75714286 0.77142857 0.78571429 0.8 0.81428571 0.82857143 0.84285714 0.85714286 0.87142857 0.88571429 0.9 0.91428571 0.92857143 0.94285714 0.95714286 0.97142857 0.98571429 1 1 1 1 1 1
  arc A62 (-10.213, 9.9377) -> (-10.8376, 9.2525) centre (0, 0) ccw
  spline S31 degree 5 poles (-10.8376, 9.2525) (-10.8354, 9.2453) (-10.8311, 9.2309) (-10.8245, 9.2092) (-10.8156, 9.1805) (-10.8044, 9.1447) (-10.793, 9.109) (-10.7814, 9.0734) (-10.7697, 9.0379) (-10.7578, 9.0026) (-10.7457, 8.9674) (-10.7335, 8.9322) (-10.7211, 8.8973) (-10.7086, 8.8624) (-10.6959, 8.8277) (-10.6831, 8.793) (-10.67, 8.7586) (-10.6569, 8.7242) (-10.6435, 8.69) (-10.63, 8.6559) (-10.6163, 8.6219) (-10.6025, 8.5881) (-10.5885, 8.5544) (-10.5743, 8.5208) (-10.56, 8.4874) (-10.5455, 8.4541) (-10.5308, 8.421) (-10.516, 8.388) (-10.501, 8.3551) (-10.4858, 8.3224) (-10.4705, 8.2899) (-10.4549, 8.2575) (-10.4393, 8.2252) (-10.4234, 8.1932) (-10.4074, 8.1612) (-10.3912, 8.1295) (-10.3748, 8.0979) (-10.3582, 8.0664) (-10.3415, 8.0351) (-10.3246, 8.004) (-10.3075, 7.9731) (-10.2902, 7.9423) (-10.2728, 7.9117) (-10.2551, 7.8813) (-10.2373, 7.8511) (-10.2193, 7.8211) (-10.2011, 7.7913) (-10.1827, 7.7616) (-10.1641, 7.7321) (-10.1453, 7.7029) (-10.1264, 7.6738) (-10.1072, 7.645) (-10.0878, 7.6164) (-10.0682, 7.5881) (-10.0483, 7.5599) (-10.0283, 7.532) (-10.0081, 7.5043) (-9.9877, 7.4768) (-9.967, 7.4496) (-9.9462, 7.4226) (-9.9251, 7.3959) (-9.9037, 7.3695) (-9.8819, 7.3436) (-9.8598, 7.318) (-9.8374, 7.2928) (-9.8148, 7.2678) (-9.7921, 7.243) (-9.7692, 7.2184) (-9.7461, 7.1941) (-9.7226, 7.1703) (-9.6984, 7.1473) (-9.6783, 7.1298) (-9.6628, 7.1173) (-9.6522, 7.1093) (-9.6468, 7.1053) knots -1 -1 -1 -1 -1 -1 -0.98571429 -0.97142857 -0.95714286 -0.94285714 -0.92857143 -0.91428571 -0.9 -0.88571429 -0.87142857 -0.85714286 -0.84285714 -0.82857143 -0.81428571 -0.8 -0.78571429 -0.77142857 -0.75714286 -0.74285714 -0.72857143 -0.71428571 -0.7 -0.68571429 -0.67142857 -0.65714286 -0.64285714 -0.62857143 -0.61428571 -0.6 -0.58571429 -0.57142857 -0.55714286 -0.54285714 -0.52857143 -0.51428571 -0.5 -0.48571429 -0.47142857 -0.45714286 -0.44285714 -0.42857143 -0.41428571 -0.4 -0.38571429 -0.37142857 -0.35714286 -0.34285714 -0.32857143 -0.31428571 -0.3 -0.28571429 -0.27142857 -0.25714286 -0.24285714 -0.22857143 -0.21428571 -0.2 -0.18571429 -0.17142857 -0.15714286 -0.14285714 -0.12857143 -0.11428571 -0.1 -0.08571429 -0.07142857 -0.05714286 -0.04285714 -0.02857143 -0.01428571 0 0 0 0 0 0
  line L31 (-9.6468, 7.1053) -> (-9.3973, 6.9212)
  arc A63 (-9.1973, 5.8483) -> (-9.3973, 6.9212) centre (-9.8724, 6.2775) ccw
  arc A64 (-9.1973, 5.8483) -> (-9.3347, 5.6263) centre (0, 0) ccw
  arc A65 (-10.3844, 5.3271) -> (-9.3347, 5.6263) centre (-10.0199, 6.0393) ccw
  line L32 (-10.3844, 5.3271) -> (-10.6604, 5.4683)
  spline S32 degree 5 poles (-10.6604, 5.4683) (-10.6663, 5.4714) (-10.6782, 5.4773) (-10.6964, 5.4856) (-10.721, 5.4958) (-10.7523, 5.5072) (-10.7841, 5.5177) (-10.8162, 5.5275) (-10.8484, 5.537) (-10.8807, 5.5464) (-10.9131, 5.5554) (-10.9457, 5.5642) (-10.9784, 5.5726) (-11.0114, 5.5805) (-11.0445, 5.5879) (-11.0778, 5.595) (-11.1113, 5.6016) (-11.1449, 5.6079) (-11.1786, 5.6139) (-11.2124, 5.6197) (-11.2463, 5.6252) (-11.2803, 5.6304) (-11.3144, 5.6353) (-11.3487, 5.6399) (-11.383, 5.6442) (-11.4175, 5.6483) (-11.4521, 5.652) (-11.4867, 5.6555) (-11.5215, 5.6588) (-11.5563, 5.6618) (-11.5912, 5.6645) (-11.6262, 5.667) (-11.6613, 5.6692) (-11.6964, 5.6712) (-11.7316, 5.673) (-11.767, 5.6745) (-11.8023, 5.6758) (-11.8378, 5.6768) (-11.8733, 5.6776) (-11.9089, 5.6782) (-11.9446, 5.6785) (-11.9803, 5.6786) (-12.0161, 5.6785) (-12.052, 5.6782) (-12.0879, 5.6776) (-12.1239, 5.6769) (-12.1599, 5.6759) (-12.196, 5.6747) (-12.2321, 5.6732) (-12.2683, 5.6716) (-12.3046, 5.6697) (-12.3409, 5.6677) (-12.3773, 5.6654) (-12.4137, 5.6629) (-12.4501, 5.6602) (-12.4866, 5.6573) (-12.5232, 5.6542) (-12.5597, 5.6509) (-12.5964, 5.6474) (-12.6331, 5.6437) (-12.6698, 5.6398) (-12.7065, 5.6356) (-12.7433, 5.6313) (-12.7802, 5.6268) (-12.817, 5.6221) (-12.8539, 5.6172) (-12.8909, 5.6121) (-12.9279, 5.6067) (-12.9649, 5.6012) (-13.0019, 5.5955) (-13.039, 5.5896) (-13.0687, 5.5848) (-13.0909, 5.581) (-13.1058, 5.5785) (-13.1132, 5.5772) knots 0 0 0 0 0 0 0.01428571 0.02857143 0.04285714 0.05714286 0.07142857 0.08571429 0.1 0.11428571 0.12857143 0.14285714 0.15714286 0.17142857 0.18571429 0.2 0.21428571 0.22857143 0.24285714 0.25714286 0.27142857 0.28571429 0.3 0.31428571 0.32857143 0.34285714 0.35714286 0.37142857 0.38571429 0.4 0.41428571 0.42857143 0.44285714 0.45714286 0.47142857 0.48571429 0.5 0.51428571 0.52857143 0.54285714 0.55714286 0.57142857 0.58571429 0.6 0.61428571 0.62857143 0.64285714 0.65714286 0.67142857 0.68571429 0.7 0.71428571 0.72857143 0.74285714 0.75714286 0.77142857 0.78571429 0.8 0.81428571 0.82857143 0.84285714 0.85714286 0.87142857 0.88571429 0.9 0.91428571 0.92857143 0.94285714 0.95714286 0.97142857 0.98571429 1 1 1 1 1 1
  arc A66 (-13.1132, 5.5772) -> (-13.4482, 4.7127) centre (0, 0) ccw
  spline S33 degree 5 poles (-13.4482, 4.7127) (-13.4435, 4.7068) (-13.4342, 4.6949) (-13.4203, 4.6771) (-13.4016, 4.6535) (-13.3782, 4.6242) (-13.3547, 4.595) (-13.331, 4.566) (-13.3073, 4.5372) (-13.2834, 4.5085) (-13.2595, 4.48) (-13.2354, 4.4517) (-13.2112, 4.4235) (-13.1869, 4.3955) (-13.1626, 4.3677) (-13.1381, 4.3401) (-13.1135, 4.3126) (-13.0888, 4.2854) (-13.0639, 4.2583) (-13.039, 4.2314) (-13.014, 4.2046) (-12.9889, 4.1781) (-12.9637, 4.1517) (-12.9383, 4.1255) (-12.9129, 4.0996) (-12.8873, 4.0738) (-12.8617, 4.0482) (-12.8359, 4.0228) (-12.8101, 3.9975) (-12.7841, 3.9725) (-12.7581, 3.9477) (-12.7319, 3.9231) (-12.7056, 3.8987) (-12.6792, 3.8745) (-12.6528, 3.8505) (-12.6262, 3.8268) (-12.5995, 3.8032) (-12.5727, 3.7799) (-12.5458, 3.7568) (-12.5188, 3.7338) (-12.4917, 3.7112) (-12.4644, 3.6887) (-12.4371, 3.6665) (-12.4097, 3.6446) (-12.3821, 3.6228) (-12.3545, 3.6013) (-12.3267, 3.5801) (-12.2989, 3.5591) (-12.2709, 3.5383) (-12.2429, 3.5178) (-12.2147, 3.4976) (-12.1864, 3.4776) (-12.1579, 3.458) (-12.1294, 3.4386) (-12.1008, 3.4195) (-12.072, 3.4008) (-12.0431, 3.3822) (-12.0142, 3.364) (-11.9851, 3.346) (-11.9559, 3.3283) (-11.9266, 3.3111) (-11.8971, 3.2943) (-11.8674, 3.2779) (-11.8376, 3.2621) (-11.8076, 3.2466) (-11.7775, 3.2315) (-11.7473, 3.2166) (-11.7171, 3.2019) (-11.6868, 3.1876) (-11.6563, 3.1739) (-11.6254, 3.1612) (-11.6004, 3.1522) (-11.5813, 3.1461) (-11.5685, 3.1424) (-11.5621, 3.1407) knots -1 -1 -1 -1 -1 -1 -0.98571429 -0.97142857 -0.95714286 -0.94285714 -0.92857143 -0.91428571 -0.9 -0.88571429 -0.87142857 -0.85714286 -0.84285714 -0.82857143 -0.81428571 -0.8 -0.78571429 -0.77142857 -0.75714286 -0.74285714 -0.72857143 -0.71428571 -0.7 -0.68571429 -0.67142857 -0.65714286 -0.64285714 -0.62857143 -0.61428571 -0.6 -0.58571429 -0.57142857 -0.55714286 -0.54285714 -0.52857143 -0.51428571 -0.5 -0.48571429 -0.47142857 -0.45714286 -0.44285714 -0.42857143 -0.41428571 -0.4 -0.38571429 -0.37142857 -0.35714286 -0.34285714 -0.32857143 -0.31428571 -0.3 -0.28571429 -0.27142857 -0.25714286 -0.24285714 -0.22857143 -0.21428571 -0.2 -0.18571429 -0.17142857 -0.15714286 -0.14285714 -0.12857143 -0.11428571 -0.1 -0.08571429 -0.07142857 -0.05714286 -0.04285714 -0.02857143 -0.01428571 0 0 0 0 0 0
  line L33 (-11.5621, 3.1407) -> (-11.263, 3.0591)
  arc A67 (-10.6889, 2.1309) -> (-11.263, 3.0591) centre (-11.4734, 2.2873) ccw
  circle A68 centre (0, 0) radius 0.5
  circle A69 centre (0, 0) radius 1
  dimension "d43" = 2
  constraint coincident A0.centre A2.centre
  measures "d43" diameter of A69
extrude "Extrude10" cut sketch "Sketch8" against normal blind 4 contours A69 in component "Spur Gear (17 teeth)"